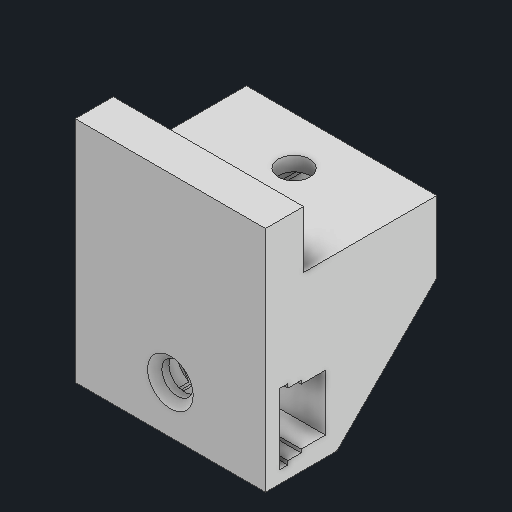
# Autodesk Inventor part: Fixação capa alumínio reta com aba
Saved by Autodesk Inventor 2026.1 (Build 301233000, 233)
## iProperties
Created: 2025-09-01
Part Number: Fixação capa alumínio reta com aba
Material: Genérico
Document SubType Name: Modeling
Designer: Cliente
Mass: 4.30583 g
Surface Area: 28.2741 cm^2
Volume: 4.30583 cm^3
Density: 1 g/cm^3
Appearance: Padrão
Author: Cliente
Autodesk Inventor part; units mm, degrees
ref_plane "YZ Plane" through (0, 0, 0) normal (1, 0, 0) x (0, 1, 0)
ref_plane "XZ Plane" through (0, 0, 0) normal (0, 1, 0) x (-1, 0, 0)
ref_plane "XY Plane" through (0, 0, 0) normal (0, 0, 1) x (1, 0, 0)
sketch "Esboço1" plane through (0, 0, 0) normal (0, 1, 0) x (-1, 0, 0)
  line L0 (0, 0) -> (0, -13)
  circle A0 centre (0, -13) radius 1.65
  line L1 (10, -18) -> (-10, -18)
  line L2 (10, -18) -> (10, 0)
  line L3 (-10, -18) -> (-10, 0)
  line L4 (10, 0) -> (-10, 0)
  point P0 (0, 0)
  dimension "d2" = 20
  dimension "d3" = 13
  dimension "d4" = 3.3
  dimension "d6" = 20
  dimension "d68" = 18
  constraints: 10 end point, 2 coincident, 2 horizontal alignment, 1 centre point, 1 horizontal, 1 midpoint, 1 perpendicular, 1 vertical
  measures "d2" distance of L3.end L2.end
  measures "d3" distance of L0.start L0.end
  measures "d4" diameter of A0
  measures "d6" distance of L1.start L1.end
  measures "d68" distance between parallel lines of L4 L1
extrude "Extrusão1" add sketch "Esboço1" against normal blind 7.5
sketch "Esboço2" plane through (10, 0, -18) normal (0, 0, -1) x (-1, 0, 0)
  line L0 (10, 0) -> (10, -1.5)
  line L1 (6.3, -2.35) -> (13.7, -2.35)
  line L2 (13.7, -2.35) -> (13.7, -1.5)
  line L3 (13.7, -1.5) -> (6.3, -1.5)
  line L4 (6.3, -1.5) -> (6.3, -2.35)
  line L5 (6.3, -2.35) -> (13.7, -1.5) construction
  line L6 (13.7, -2.35) -> (6.3, -1.5) construction
  line L7 (13.3, -3.75) -> (6.7, -3.75)
  line L8 (6.7, -3.75) -> (6.7, -2.35)
  line L9 (6.7, -2.35) -> (13.3, -2.35)
  line L10 (13.3, -2.35) -> (13.3, -3.75)
  line L11 (13.3, -3.75) -> (6.7, -2.35) construction
  line L12 (6.7, -3.75) -> (13.3, -2.35) construction
  line L13 (7.05, -6.3) -> (12.95, -6.3)
  line L14 (12.95, -6.3) -> (12.95, -3.75)
  line L15 (12.95, -3.75) -> (7.05, -3.75)
  line L16 (7.05, -3.75) -> (7.05, -6.3)
  line L17 (7.05, -6.3) -> (12.95, -3.75) construction
  line L18 (12.95, -6.3) -> (7.05, -3.75) construction
  point P0 (10, -1.925)
  point P1 (10, -3.05)
  point P2 (10, -2.35)
  point P3 (10, -5.025)
  point P4 (10, -3.75)
  point P5 (6.7, -2.35)
  point P6 (12.95, -3.75)
  point P7 (13.3, -2.35)
  dimension "d9" = 1.5
  dimension "d10" = 0.85
  dimension "d11" = 7.4
  dimension "d12" = 6.6
  dimension "d13" = 1.4
  dimension "d14" = 5.9
  dimension "d15" = 2.55
  constraints: 38 end point, 11 midpoint, 6 parallel, 3 horizontal, 3 perpendicular, 1 vertical
  measures "d9" distance of L0.end L0.start
  measures "d10" distance of L1.end L2.end
  measures "d11" distance of L1.start L1.end
  measures "d12" distance of L8.end L9.end
  measures "d13" distance of L7.end L8.end
  measures "d14" distance of L15.end L14.end
  measures "d15" distance of L14.end L13.end
extrude "Extrusão2" cut sketch "Esboço2" against normal blind 5
sketch "Esboço3" plane through (-3.7, -2.35, -18) normal (0, 1, 0) x (1, 0, 0)
  line L0 (7, 0) -> (7.4, 0) projected
  line L1 (7, 0) -> (7, -5) projected
  line L2 (7, -5) -> (7.4, -5) projected
  line L3 (7.4, 0) -> (7.4, -5) projected
  arc A0 (5.35, -5) -> (2.05, -5) centre (3.7, -5) ccw projected
  arc A1 (5.35, -5) -> (2.05, -5) centre (3.7, -5) ccw projected
  circle A2 centre (3.7, -5) radius 1.65 projected
  circle A3 centre (3.7, -5) radius 1.65 projected
  line L4 (0, -5) -> (0.4, -5) projected
  circle A4 centre (3.7, -5) radius 3.7
  point P0 (3.7, -18)
  point P1 (5.35, -5)
  constraints: 1 coincident, 1 horizontal alignment, 2 other
extrude "Extrusão3" cut sketch "Esboço3" along normal up to surface (0.85 mm away) contours A4 L2 L1 | L1 L2 A4 | A2 A0
sketch "Esboço4" plane through (2.95, -3.75, -18) normal (0, 1, 0) x (1, 0, 0)
  line L0 (0, 0) -> (0.35, 0) projected
  line L1 (0, 0) -> (0, -5) projected
  line L2 (0, -5) -> (0.35, -5) projected
  line L3 (0.35, 0) -> (0.35, -5) projected
  circle A0 centre (-2.95, -5) radius 1.65 projected
  circle A1 centre (-2.95, -5) radius 1.65 projected
  circle A2 centre (-2.95, -5) radius 3.3
  point P0 (-2.95, -18)
  constraints: 1 coincident, 1 horizontal alignment, 2 other
extrude "Extrusão4" cut sketch "Esboço4" along normal up to surface (2.25 mm away) contours A2 L2 L1 | L1 L2 A2
sketch "Esboço5" plane through (-2.95, -6.3, -18) normal (0, 1, 0) x (1, 0, 0)
  circle A0 centre (2.95, -5) radius 1.65 projected
  circle A1 centre (2.95, -5) radius 1.65 projected
  arc A2 (4.6, -5) -> (1.3, -5) centre (2.95, -5) ccw projected
  line L0 (4.6, -5) -> (5.9, -5) projected
  line L1 (5.9, 0) -> (5.9, -5) projected
  line L2 (0, 0) -> (5.9, 0) projected
  line L3 (0, 0) -> (0, -5) projected
  line L4 (2.95, -1.5936) -> (5.9, -3.2968)
  line L5 (5.9, -3.2968) -> (5.9, -6.7032)
  line L6 (5.9, -6.7032) -> (2.95, -8.4064)
  line L7 (2.95, -8.4064) -> (0, -6.7032)
  line L8 (0, -6.7032) -> (0, -3.2968)
  line L9 (0, -3.2968) -> (2.95, -1.5936)
  line L10 (0, -5) -> (1.3, -5) projected
  point P0 (2.95, -18)
  point P1 (0, -5)
  point P2 (5.9, -5)
  point P3 (0, -3.2968)
  constraints: 12 end point, 1 coincident, 1 point on line, 1 vertical, 13 other
extrude "Extrusão5" cut sketch "Esboço5" along normal up to surface (4.8 mm away) contours A0 | L0 L5 L6 L7 L8 L10 A0 | A0 L10 L3 L9 L4 L1 L0
sketch "Esboço6" plane through (0, 0, 0) normal (0, 1, 0) x (1, 0, 0)
  line L0 (10, 0) -> (10, 18) projected
  line L1 (10, 18) -> (-10, 18) projected
  line L2 (-10, 18) -> (-10, 0) projected
  circle A0 centre (0, 13) radius 1.65 projected
  line L3 (-10, 0) -> (10, 0)
  line L4 (-10, 0) -> (10, 0) projected
  line L5 (-10, 7.5) -> (10, 7.5)
  point P0 (0, 0)
  dimension "d69" = 7.5
  constraints: 4 end point, 2 point on line, 1 horizontal, 1 perpendicular
  measures "d69" distance between parallel lines of L3 L5
extrude "Extrusão6" add sketch "Esboço6" against normal blind 18 contours L3 L2 L5 L0
sketch "Esboço8" plane through (0, 0, 0) normal (0, 1, 0) x (1, 0, 0)
  circle A0 centre (0, 13) radius 1.65 projected
  line L0 (10, 0) -> (10, 18) projected
  line L1 (10, 18) -> (-10, 18) projected
  line L2 (-10, 18) -> (-10, 0) projected
  line L3 (-10, 0) -> (10, 0) projected
  point P0 (0, 0)
sketch "Esboço9" plane through (10, 0, 0) normal (1, 0, 0) x (0, 0, -1)
  line L0 (0, -13) -> (1.5, -13)
  line L1 (2.35, -16.7) -> (1.5, -16.7)
  line L2 (1.5, -16.7) -> (1.5, -9.3)
  line L3 (1.5, -9.3) -> (2.35, -9.3)
  line L4 (2.35, -9.3) -> (2.35, -16.7)
  line L5 (2.35, -16.7) -> (1.5, -9.3) construction
  line L6 (1.5, -16.7) -> (2.35, -9.3) construction
  line L7 (3.75, -16.3) -> (2.35, -16.3)
  line L8 (2.35, -16.3) -> (2.35, -9.7)
  line L9 (2.35, -9.7) -> (3.75, -9.7)
  line L10 (3.75, -9.7) -> (3.75, -16.3)
  line L11 (3.75, -16.3) -> (2.35, -9.7) construction
  line L12 (2.35, -16.3) -> (3.75, -9.7) construction
  line L13 (6.3, -15.95) -> (3.75, -15.95)
  line L14 (3.75, -15.95) -> (3.75, -10.05)
  line L15 (3.75, -10.05) -> (6.3, -10.05)
  line L16 (6.3, -10.05) -> (6.3, -15.95)
  line L17 (6.3, -15.95) -> (3.75, -10.05) construction
  line L18 (3.75, -15.95) -> (6.3, -10.05) construction
  line L19 (0, 0) -> (0, -18) projected
  line L20 (7.5, -7.5) -> (7.5, -18) projected
  line L21 (7.5, -18) -> (0, -18) projected
  point P0 (1.925, -13)
  point P1 (3.05, -13)
  point P2 (5.025, -13)
  point P3 (2.35, -13)
  point P4 (3.75, -13)
  point P5 (3.75, -10.05)
  point P6 (2.35, -9.7)
  point P7 (2.35, -16.3)
  point P8 (3.75, -15.95)
  dimension "d28" = 1.5
  dimension "d36" = 0.85
  dimension "d37" = 7.4
  dimension "d38" = 1.4
  dimension "d39" = 6.6
  dimension "d40" = 2.55
  dimension "d41" = 5.9
  dimension "d70" = 5
  constraints: 38 end point, 11 midpoint, 6 parallel, 4 horizontal, 3 perpendicular, 1 point on line
  measures "d28" distance of L0.end L0.start
  measures "d36" distance of L2.end L3.end
  measures "d37" distance of L1.end L2.end
  measures "d38" distance of L8.end L9.end
  measures "d39" distance of L7.end L8.end
  measures "d40" distance of L14.end L15.end
  measures "d41" distance of L13.end L14.end
  measures "d70" distance between parallel lines of L21 L0
extrude "Extrusão8" cut sketch "Esboço9" against normal blind 10
sketch "Esboço10" plane through (10, -9.7, -2.35) normal (0, 0, 1) x (1, 0, 0)
  line L0 (0, 0.4) -> (0, 0) projected
  line L1 (0, 0.4) -> (-10, 0.4) projected
  line L2 (-10, 0.4) -> (-10, 0) projected
  line L3 (0, 0) -> (-10, 0) projected
  line L4 (0, -6.6) -> (0, -7) projected
  line L5 (0, -6.6) -> (-10, -6.6) projected
  line L6 (-10, -6.6) -> (-10, -7) projected
  line L7 (0, -7) -> (-10, -7) projected
  line L8 (-10, 0.4) -> (-10, 0) projected
  line L9 (-10, -7) -> (-10, 0.4) projected
  line L10 (-10, -6.6) -> (-10, -7) projected
  line L11 (-10, -6.25) -> (-10, -6.6) projected
  line L12 (-10, -0.35) -> (-10, -6.25) projected
  line L13 (-10, 0) -> (-10, -0.35) projected
  circle A0 centre (-10, -3.3) radius 3.7
  point P0 (-10, 9.7)
  constraints: 1 midpoint, 1 vertical alignment, 2 other
extrude "Extrusão9" cut sketch "Esboço10" along normal up to surface (0.85 mm away) contours A0 L3 L2 | L2 L9 L6 A0 | A0 L5 L9 L3 | L6 L5 A0
sketch "Esboço11" plane through (10, -10.05, -3.75) normal (0, 0, 1) x (1, 0, 0)
  line L0 (0, -5.9) -> (0, -6.25) projected
  line L1 (0, -5.9) -> (-10, -5.9) projected
  line L2 (-10, -5.9) -> (-10, -6.25) projected
  line L3 (0, -6.25) -> (-10, -6.25) projected
  line L4 (0, 0.35) -> (0, 0) projected
  line L5 (0, 0.35) -> (-10, 0.35) projected
  line L6 (-10, 0.35) -> (-10, 0) projected
  line L7 (0, 0) -> (-10, 0) projected
  line L8 (-10, 0.35) -> (-10, -6.25) projected
  line L9 (-10, -5.9) -> (-10, -6.25) projected
  line L10 (-10, 0) -> (-10, -5.9) projected
  line L11 (-10, 0.35) -> (-10, 0) projected
  circle A0 centre (-10, -2.95) radius 3.3
  point P0 (-10, 10.05)
  constraints: 1 midpoint, 1 vertical alignment, 2 other
extrude "Extrusão10" cut sketch "Esboço11" along normal up to surface (1.4 mm away) contours A0 L2 L1 | L1 L8 L7 A0 | A0 L6 L8 L2 | A0 L7 L6
sketch "Esboço12" plane through (10, -15.95, -6.3) normal (0, 0, 1) x (1, 0, 0)
  line L0 (0, 5.9) -> (0, 0) projected
  line L1 (0, 5.9) -> (-10, 5.9) projected
  line L2 (-10, 5.9) -> (-10, 0) projected
  line L3 (0, 0) -> (-10, 0) projected
  line L4 (-6.5936, 2.95) -> (-8.2968, 0)
  line L5 (-8.2968, 0) -> (-11.7032, 0)
  line L6 (-11.7032, 0) -> (-13.4064, 2.95)
  line L7 (-13.4064, 2.95) -> (-11.7032, 5.9)
  line L8 (-11.7032, 5.9) -> (-8.2968, 5.9)
  line L9 (-8.2968, 5.9) -> (-6.5936, 2.95)
  point P0 (-10, 15.95)
  point P1 (-10, 2.95)
  point P2 (-10, 5.9)
  constraints: 12 end point, 1 horizontal, 1 midpoint, 1 point on line, 13 other
extrude "Extrusão11" cut sketch "Esboço12" along normal up to surface (3.95 mm away) contours L9 L4 L3 L2 L1 | L2 L5 L6 L7 L8
sketch "Esboço13" plane through (10, -7.5, 0) normal (0, 0, 1) x (1, 0, 0)
  line L0 (-20, -10.5) -> (0, -10.5) projected
  line L1 (-10, -10.5) -> (-10, -5.5)
  circle A0 centre (-10, -5.5) radius 1.65
  line L2 (0, -10.5) -> (0, 7.5) projected
  line L3 (0, 7.5) -> (-20, 7.5) projected
  line L4 (-20, 7.5) -> (-20, -10.5) projected
  point P0 (-10, 7.5)
  dimension "d50" = 5
  dimension "d52" = 3.3
  constraints: 2 end point, 1 centre point, 1 coincident, 1 midpoint, 1 vertical
  measures "d50" distance of L1.start L1.end
  measures "d52" diameter of A0
extrude "Extrusão12" cut sketch "Esboço13" against normal through all contours A0
sketch "Esboço14" plane through (10, 0, 0) normal (1, 0, 0) x (0, 0, -1)
  line L0 (0, 0) -> (18, 0) projected
  line L1 (18, -7.5) -> (7.5, -7.5) projected
  line L2 (18, 0) -> (18, -7.5) projected
  line L3 (7.5, -18) -> (18, -7.5)
  line L4 (7.5, -18) -> (0, -18) projected
  line L5 (7.5, -7.5) -> (7.5, -18) projected
  line L6 (0, 0) -> (0, -18) projected
  point P0 (0, 0)
  constraints: 2 end point
extrude "Extrusão13" add sketch "Esboço14" against normal blind 2 contours L3 L5 L1
sketch "Esboço15" plane through (-10, 0, -18) normal (-1, 0, 0) x (0, 0, 1)
  line L0 (0, 0) -> (0, -7.5) projected
  line L1 (10.5, -7.5) -> (0, -7.5) projected
  line L2 (10.5, -7.5) -> (10.5, -18) projected
  line L3 (0, 0) -> (18, 0) projected
  line L4 (18, -18) -> (10.5, -18) projected
  line L5 (18, 0) -> (18, -18) projected
  line L6 (0, -7.5) -> (10.5, -18) projected
  line L7 (0, -7.5) -> (10.5, -18)
  constraints: 2 end point, 1 collinear
extrude "Extrusão14" add sketch "Esboço15" against normal blind 2 contours L1 L2 L6
sketch "Esboço16" plane through (0, 0, 0) normal (0, 1, 0) x (1, 0, 0)
  line L0 (-10, 0) -> (-10, 4)
  circle A0 centre (0, 13) radius 1.65 projected
  line L1 (10, 0) -> (10, 18) projected
  line L2 (10, 18) -> (-10, 18) projected
  line L3 (-10, 4) -> (10, 4)
  line L4 (-10, 18) -> (-10, 0) projected
  line L5 (-10, 0) -> (10, 0) projected
  point P0 (0, 0)
  dimension "d62" = 4
  constraints: 4 end point, 1 perpendicular, 1 point on line, 1 vertical
  measures "d62" distance of L0.start L0.end
extrude "Extrusão15" add sketch "Esboço16" along normal blind 6 contours L0 L3 L1 L5
chamfer "Chanfro3" distance 0.75 angle 45 1 edges at (-1.65, -13, 0)
